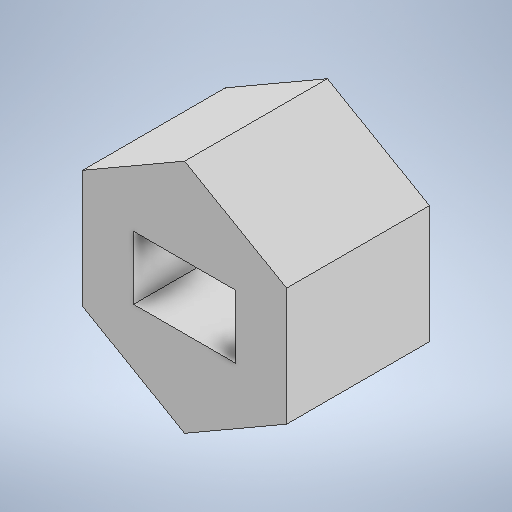
# Autodesk Inventor part: TestPiece_Hub1
Saved by Autodesk Inventor 2025.3 (Build 293356000, 356)
## iProperties
Created: 2025-09-27
Part Number: TestPiece_Hub1
Material: 一般
Document SubType Name: Modeling
Designer: yamashita1
Density: 1 g/cm^3
Appearance: 既定
Author: yamashita1
Autodesk Inventor part; units mm, degrees
ref_plane "YZ Plane" through (0, 0, 0) normal (1, 0, 0) x (0, 1, 0)
ref_plane "XZ Plane" through (0, 0, 0) normal (0, 1, 0) x (-1, 0, 0)
ref_plane "XY Plane" through (0, 0, 0) normal (0, 0, 1) x (1, 0, 0)
sketch "スケッチ1" plane through (0, 0, 0) normal (0, 0, 1) x (1, 0, 0)
  line L0 (5, -2.8868) -> (0, -5.7735)
  line L1 (0, -5.7735) -> (-5, -2.8868)
  line L2 (-5, -2.8868) -> (-5, 2.8868)
  line L3 (-5, 2.8868) -> (0, 5.7735)
  line L4 (0, 5.7735) -> (5, 2.8868)
  line L5 (5, 2.8868) -> (5, -2.8868)
  line L6 (-2.5, 1.55) -> (2.5, 1.55)
  line L7 (2.5, 1.55) -> (2.5, -1.55)
  line L8 (2.5, -1.55) -> (-2.5, -1.55)
  line L9 (-2.5, -1.55) -> (-2.5, 1.55)
  point P0 (0, 0)
  point P1 (0, 0)
  point P2 (0, 1.55)
  point P3 (2.5, 0)
  dimension "d0" = 10
  dimension "d1" = 5
  dimension "d2" = 3.1
  constraints: 20 end point, 2 midpoint, 2 parallel, 2 vertical alignment, 1 coincident, 1 horizontal, 1 horizontal alignment, 1 perpendicular, 13 other
  measures "d0" distance between parallel lines of L5 L2
  measures "d1" distance of L7.end L8.end
  measures "d2" distance of L6.end L7.end
extrude "押し出し1" add sketch "スケッチ1" along normal blind 7
